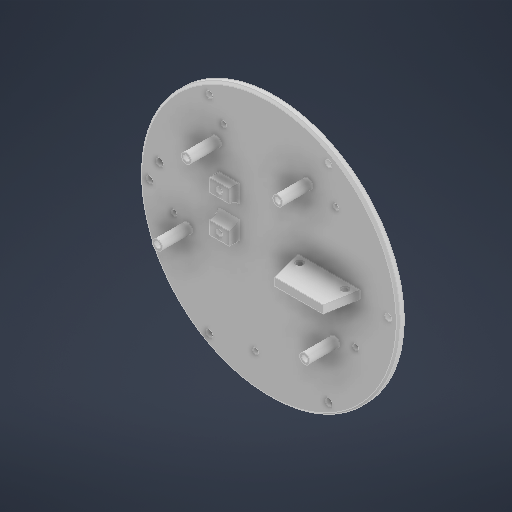
# Autodesk Inventor part: Topf_Boden_210715
Saved by Autodesk Inventor 2027 (Build 310192000, 192)
## iProperties
Created: 2021-02-06
Part Number: Topf_Boden_210715
Material: Generisch
Document SubType Name: Modeling
Designer: uhlma
Density: 1 g/cm^3
Appearance: Vorgabe
Author: uhlma
Autodesk Inventor part; units mm, degrees
ref_plane "YZ Plane" through (0, 0, 0) normal (1, 0, 0) x (0, 1, 0)
ref_plane "XZ Plane" through (0, 0, 0) normal (0, 1, 0) x (-1, 0, 0)
ref_plane "XY Plane" through (0, 0, 0) normal (0, 0, 1) x (1, 0, 0)
sketch "Skizze1" plane through (0, 0, 0) normal (0, 0, 1) x (1, 0, 0)
  circle A0 centre (0, 0) radius 65
  dimension "d0" = 130
  constraints: 1 centre point, 1 coincident
  measures "d0" diameter of A0
extrude "Extrusion1" add sketch "Skizze1" along normal blind 3
sketch "Skizze16" plane through (0, 0, 0) normal (0, 0, -1) x (-1, 0, 0)
  line L0 (0, 0) -> (0, -17.5411) construction
  line L1 (0, 0) -> (-21.264, -36.8303) construction
  point P0 (-30, -51.9615)
  dimension "d93" = 60
  dimension "d188" = 30
  constraints: 4 end point, 1 point on line, 1 vertical
  measures "d93" distance of L0.start point (-30, -51.962)
  measures "d188" angle of L0 L1
hole "Bohrung2" at (30, -51.9615, 0) direction (0, 0, 1) diameter 3.3 end through all
pattern_circular "Runde Anordnung1" count 6 over 360 about axis through (0, 0, -10) along (0, 0, 1) of "Bohrung2"
sketch "Skizze2" plane through (0, 0, 3) normal (0, 0, 1) x (1, 0, 0)
  line L0 (42.1, -1) -> (18.7, -1)
  line L1 (18.7, -1) -> (18.7, 1)
  line L2 (18.7, 1) -> (42.1, 1)
  line L3 (42.1, 1) -> (42.1, -1)
  line L4 (42.1, -1) -> (18.7, 1) construction
  line L5 (18.7, -1) -> (42.1, 1) construction
  point P0 (0, 0)
  point P1 (30.4, 0)
  dimension "d378" = 2
  dimension "d379" = 23.4
  dimension "d413" = 30.4
  constraints: 12 end point, 2 midpoint, 2 parallel, 1 horizontal, 1 horizontal alignment, 1 perpendicular
  measures "d378" distance of L0.end L1.end
  measures "d379" distance of L0.start L0.end
  measures "d413" distance of point (0, 0) point (30.4, 0)
extrude "Extrusion2" cut sketch "Skizze2" against normal through all
sketch "Skizze3" plane through (0, 0, 3) normal (0, 0, 1) x (1, 0, 0)
  line L0 (45.9, 1) -> (14.9, 1)
  line L1 (14.9, 1) -> (14.9, 5)
  line L2 (14.9, 5) -> (45.9, 5)
  line L3 (45.9, 5) -> (45.9, 1)
  line L4 (45.9, 1) -> (14.9, 5) construction
  line L5 (14.9, 1) -> (45.9, 5) construction
  line L6 (18.7, 1) -> (42.1, 1) projected
  line L7 (42.1, -1) -> (18.7, -1) projected
  point P0 (0, 0)
  point P1 (30.4, 3)
  point P2 (30.4, 14)
  point P3 (30.4, -1)
  dimension "d370" = 31
  dimension "d371" = 4
  constraints: 12 end point, 3 midpoint, 2 parallel, 2 vertical alignment, 1 horizontal, 1 perpendicular, 2 other
  measures "d370" distance of L1.end L2.end
  measures "d371" distance of L0.end L1.end
extrude "Extrusion3" add sketch "Skizze3" along normal blind 16
sketch "Skizze31" plane through (3.8619, 5, 0) normal (0, 1, 0) x (0, 0, 1)
  circle A0 centre (6.5, 15.1381) radius 1.35
  line L0 (3, 26.5381) -> (15.9783, 26.5381) construction
  circle A1 centre (6.5, 37.9381) radius 1.35
  line L1 (3, 11.0381) -> (3, 42.0381) projected
  point P0 (0, -3.8619)
  point P1 (3, -2.5479)
  point P2 (3, 26.5381)
  dimension "d222" = 2.7
  dimension "d223" = 11.4
  dimension "d382" = 3.5
  dimension "d383" = 11.4
  constraints: 2 centre point, 2 end point, 1 horizontal, 1 midpoint, 1 symmetric about line, 1 other
  measures "d222" diameter of A0
  measures "d223" distance from line of A0.centre L0
  measures "d382" distance from line of L1 A1.centre
  measures "d383" vertical distance of A1.centre point (3, 26.538)
extrude "Extrusion29" cut sketch "Skizze31" against normal blind 10
chamfer "Fase29" distance 0.4 angle 45 4 edges at (41.8, 5, 5.15) (19, 5, 5.15) (19, 1, 5.15) (41.8, 1, 5.15)
chamfer "Fase30" distance 1 angle 45 1 edges at (-65, 0, 3)
chamfer "Chamfer35" distance 15 angle 10 1 edges at (45.9, 3, 19) measured on face at (45.9, 2.3333, 8.3333)
chamfer "Chamfer36" distance 15 angle 15 1 edges at (14.9, 3, 19) measured on face at (14.9, 3.6667, 13.6667)
sketch "Sketch49" plane through (0, 0, 3) normal (0, 0, 1) x (1, 0, 0)
  circle A0 centre (0, 0) radius 48.5 construction
  circle A1 centre (-6.7499, -48.028) radius 1.35
  line L0 (-6.7499, -48.028) -> (0, 0) construction
  line L1 (0, 0) -> (0, -62.3416) construction
  circle A2 centre (43.5915, -21.261) radius 1.35
  circle A3 centre (33.6909, 34.888) radius 1.35
  circle A4 centre (-22.7694, 42.823) radius 1.35
  circle A5 centre (-47.7632, -8.4219) radius 1.35
  dimension "d391" = 97
  dimension "d392" = 2.7
  dimension "d394" = 8
  dimension "d397" = 360
  constraints: 5 centre point, 4 end point, 1 coincident, 1 vertical, 14 other
  measures "d392" diameter of A1
  measures "d394" angle of L1 L0
extrude "Extrusion47" cut sketch "Sketch49" against normal through all
sketch "Sketch50" plane through (0, 0, 3) normal (0, 0, 1) x (1, 0, 0)
  circle A0 centre (33, -24) radius 2.5
  circle A1 centre (-41, -11.5) radius 2.5
  circle A2 centre (-26.5, 33.5) radius 2.5
  circle A3 centre (19.5, 38) radius 2.5
  circle A4 centre (33, -24) radius 1.4
  circle A5 centre (-41, -11.5) radius 1.4
  circle A6 centre (19.5, 38) radius 1.4
  circle A7 centre (-26.5, 33.5) radius 1.4
  point P0 (0, 0)
  dimension "d401" = 5
  dimension "d402" = 33
  dimension "d403" = 24
  dimension "d404" = 41
  dimension "d405" = 11.5
  dimension "d406" = 26.5
  dimension "d407" = 33.5
  dimension "d408" = 38
  dimension "d409" = 19.5
  dimension "d412" = 2.8
  constraints: 8 centre point, 6 equal radius, 4 coincident
  measures "d401" diameter of A0
  measures "d402" horizontal distance of A0.centre point (0, 0)
  measures "d403" vertical distance of A0.centre point (0, 0)
  measures "d404" horizontal distance of point (0, 0) A1.centre
  measures "d405" vertical distance of point (0, 0) A1.centre
  measures "d406" horizontal distance of point (0, 0) A2.centre
  measures "d407" vertical distance of point (0, 0) A2.centre
  measures "d408" vertical distance of A3.centre point (0, 0)
  measures "d409" horizontal distance of point (0, 0) A3.centre
  measures "d412" diameter of A4
extrude "Extrusion48" add sketch "Sketch50" along normal blind 15
sketch "Sketch51" plane through (0, 0, 3) normal (0, 0, 1) x (1, 0, 0)
  circle A0 centre (-55, 10) radius 1.75
  circle A1 centre (-55, 20) radius 1.75
  point P0 (0, 0)
  dimension "d414" = 3.5
  dimension "d415" = 10
  dimension "d416" = 55
  dimension "d419" = 3.5
  dimension "d420" = 55
  dimension "d421" = 20
  constraints: 2 centre point
  measures "d414" diameter of A0
  measures "d415" vertical distance of point (0, 0) A0.centre
  measures "d416" horizontal distance of point (0, 0) A0.centre
  measures "d419" diameter of A1
  measures "d420" horizontal distance of point (0, 0) A1.centre
  measures "d421" vertical distance of point (0, 0) A1.centre
extrude "Extrusion49" cut sketch "Sketch51" against normal through all contours A0
sketch "Sketch52" plane through (0, 0, 3) normal (0, 0, 1) x (1, 0, 0)
  line L0 (-15, 21) -> (-25, 21)
  line L1 (-25, 21) -> (-25, -4)
  line L2 (-25, -4) -> (-15, -4)
  line L3 (-15, -4) -> (-15, 21)
  line L4 (-15, 21) -> (-25, -4) construction
  line L5 (-25, 21) -> (-15, -4) construction
  point P0 (0, 0)
  point P1 (-20, 8.5)
  dimension "d429" = 25
  dimension "d430" = 10
  dimension "d431" = 15
  dimension "d432" = 4
  constraints: 12 end point, 2 midpoint, 2 parallel, 1 horizontal, 1 perpendicular
  measures "d429" distance of L0.end L1.end
  measures "d430" distance of L1.end L2.end
  measures "d431" distance from line of point (0, 0) L3
  measures "d432" distance from line of point (0, 0) L2
extrude "Extrusion50" add sketch "Sketch52" along normal blind 5
sketch "Sketch53" plane through (-25, -4, 3) normal (-1, 0, 0) x (0, 0, 1)
  line L0 (5, 25) -> (5, 0) projected
  arc A0 (0, 9.1834) -> (0, 15.8166) centre (5, 12.5) ccw
  line L1 (0, 68) -> (0, -60) projected
  line L2 (0, 15.8166) -> (0, 9.1834)
  point P0 (-3, 4)
  point P1 (0, 9.1834)
  point P2 (5, 6.5)
  point P3 (5, 18.5)
  dimension "d435" = 12
  constraints: 2 end point, 2 point on circle, 1 centre point, 1 midpoint, 1 point on line
  measures "d435" diameter of A0
extrude "Extrusion51" cut sketch "Sketch53" against normal up to surface (10 mm away) contours L0 A0 L1
sketch "Sketch54" plane through (0, 0, 8) normal (0, 0, 1) x (1, 0, 0)
  circle A0 centre (-20, 17.75) radius 1.5
  line L0 (-15, 14.5) -> (-15, 21) projected
  line L1 (-15, 21) -> (-25, 21) projected
  circle A1 centre (-20, -0.75) radius 1.5
  line L2 (-25, -4) -> (-15, -4) projected
  line L3 (-15, -4) -> (-15, 2.5) projected
  point P0 (0, 0)
  point P1 (-15, 17.75)
  point P2 (-20, 21)
  point P3 (-20, -4)
  point P4 (-15, -0.75)
  dimension "d438" = 3
  dimension "d439" = 3
  constraints: 4 midpoint, 2 centre point, 2 horizontal alignment, 2 vertical alignment
  measures "d438" diameter of A0
  measures "d439" diameter of A1
extrude "Extrusion52" cut sketch "Sketch54" against normal up to surface (5 mm away)
